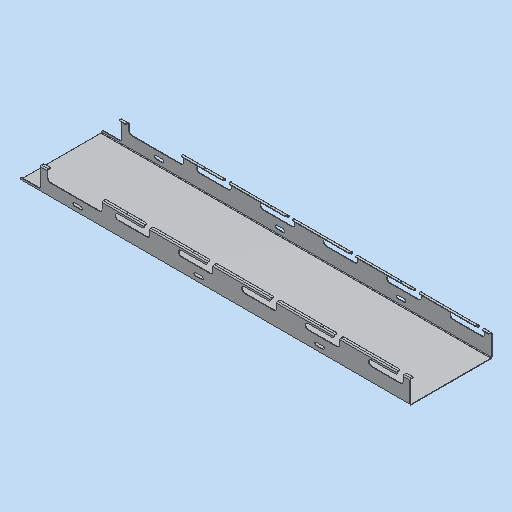
# Autodesk Inventor part: MM0948AN170_G01_103
Saved by Autodesk Inventor 2023.3 (Build 273359000, 359)
## iProperties
Part Number: MM0948AN170_G01_103
Material: 3.1645 AlCu4PbMgMn - AW 2007
Description: =<RBPARTNOTITLE2>
Document SubType Name: Blech
Designer: Benutzer
Mass: 3193.82 g
Surface Area: 11343.8 cm^2
Volume: 1120.64 cm^3
Density: 2.85 g/cm^3
Sheet Metal Rule: Standard_mm
Appearance: Aluminium AnP
Vendor: ASW
Flat Pattern Width: 135.4 cm
Flat Pattern Length: 45.5096 cm
Flat Pattern Area: 6161.99 cm^2
Sheet Metal Width: 1354,000 mm
Sheet Metal Length: 455,096 mm
Sheet Metal Area: 616199,407 mm^2
Created: 2023-03-23
RBCHANGEDESCRIPTION1: Erstfreigabe
RBCHANGENO1: 00
RBDOCUMENTTYPE: DRF
RBDOCUMENTVERSION: 00
RBDRAWINGMAINSCALE: 1:1
RBDRAWINGMISSINGSPEC: --
RBDRAWINGVOLUME: --
RBDSV1: 0850
RBGBDETAILS: 43274
RBGBEDGESIN1: +0,5
RBGBEDGESIN2: +0,2
RBGBEDGESOUT1: -0,3
RBGBEDGESOUT2: -0,1
RBMATERIAL: =<Material>
RBMATMEETS: --
RBMATNO: =<Part Number>
RBORGUNITRESPONSIBLE1: AnP/TEF1
RBPARTMADEOF: 2 x 1354 x 455,096 (FM)
RBPARTNO: SIEHE MNR
RBPARTNOTITLE1: manufactured part
RBPARTNOTITLE2: Anfertigungsteil
RBPARTSAFETYINDICATOR: --
RBSURFACE: --
RBSURFACE2: --
RBZEDGESNORM: ISO13715:2002-06
RBZGENDIMCLASS: m
RBZGENDIMNORM: ISO 2768-1:1989-11
RBZGENGEOCLASS: H
RBZGENGEONORM: ISO 2768-2:1989-11
RBZSURFACENORM: ISO13D2:2002-02
RBZTOLERANCENORM: ISO 14405-1:2010-12
AnP_Material: =<Material>
AnP_TemplVers: 20190222
AnP_Kategorie: 1
MaxAbmaße: 2 x 1354 x 455,096 (FM)
AnP_Kommentar_aktuell: =<Comments>
AnP_Material_aktuell: =<Material>
Author: FH/Wi
Keywords: =<RBPARTMADEOF>
Comments: =<RBSURFACE2>
Revision Number: 01
Autodesk Inventor part; units mm, degrees
ref_plane "YZ Plane" through (0, 0, 0) normal (1, 0, 0) x (0, 1, 0)
ref_plane "XZ Plane" through (0, 0, 0) normal (0, 1, 0) x (-1, 0, 0)
sketch "Skizze1" plane through (0, 0, 0) normal (0, 0, 1) x (1, 0, 0)
  line L0 (0, 0) -> (1654, 0)
  line L1 (1654, 0) -> (1654, 285)
  line L2 (1654, 285) -> (0, 285)
  line L3 (0, 285) -> (0, 0)
  dimension "d0" = 1654
  dimension "d1" = 285
  constraints: 8 end point, 2 parallel, 1 horizontal, 1 perpendicular
  measures "d0" distance of L2.end L1.end
  measures "d1" distance of L1.end L0.end
extrude "Extrusion1" add sketch "Skizze1" along normal blind 2
sketch "Skizze2" plane through (0, 283, 0) normal (0, 1, 0) x (-1, 0, 0)
  line L0 (-1654, 0) -> (0, 0)
  line L1 (0, 0) -> (0, 80)
  line L2 (0, 80) -> (-1654, 80)
  line L3 (-1654, 80) -> (-1654, 0)
  constraints: 4 end point, 4 other
edge flange "Lasche1" height 80 angle 90 thickness 2 bend radius 2 thickness toward (0, 1, 0) relief tear relief width 2 relief depth 1 edges at (827, 285, 2) wall of the first edge with corners at (1654, 283, 0) (0, 283, 0) (0, 283, 80) (1654, 283, 80)
bend "Biegung1"
corner "Ecke1"
sketch "Skizze3" plane through (0, 285, 78) normal (0, 0, 1) x (1, 0, 0)
  line L0 (1654, 0) -> (0, 0)
  line L1 (0, 0) -> (0, -12)
  line L2 (0, -12) -> (1654, -12)
  line L3 (1654, -12) -> (1654, 0)
  constraints: 4 end point, 4 other
edge flange "Lasche2" height 12 angle 90 thickness 2 bend radius 2 thickness toward (0, 0, 1) relief tear relief width 2 relief depth 1 edges at (827, 283, 80) wall of the first edge with corners at (1654, 285, 78) (0, 285, 78) (0, 273, 78) (1654, 273, 78)
bend "Biegung2"
corner "Ecke2"
sketch "Skizze4" plane through (1654, 2, 0) normal (0, -1, 0) x (1, 0, 0)
  line L0 (-1654, 0) -> (0, 0)
  line L1 (0, 0) -> (0, 40)
  line L2 (0, 40) -> (-1654, 40)
  line L3 (-1654, 40) -> (-1654, 0)
  constraints: 4 end point, 4 other
edge flange "Lasche3" height 40 angle 90 thickness 2 bend radius 2 thickness toward (0, -1, 0) relief tear relief width 2 relief depth 1 edges at (827, 0, 2) wall of the first edge with corners at (0, 2, 0) (1654, 2, 0) (1654, 2, 40) (0, 2, 40)
bend "Biegung3"
corner "Ecke3"
sketch "Skizze6" plane through (0, 0, 40) normal (0, -1, 0) x (1, 0, 0)
  line L0 (0, -36) -> (1654, -36) projected
  line L1 (1654, 0) -> (1654, -36) projected
  line L2 (0, 0) -> (1654, 0) projected
  line L3 (0, -36) -> (0, 0) projected
  line L4 (140, 0) -> (140, -32)
  line L5 (140, -32) -> (1514, -32)
  line L6 (1514, -32) -> (1514, 0)
  point P0 (0, -40)
  dimension "d43" = 140
  dimension "d44" = 140
  dimension "d45" = 32
  constraints: 6 end point, 2 perpendicular, 2 point on line, 1 vertical
  measures "d43" distance between parallel lines of L3 L4
  measures "d44" distance between parallel lines of L1 L6
  measures "d45" distance between parallel lines of L5 L2
extrude "Extrusion3" cut sketch "Skizze6" against normal blind 2 contours L2 L6 L5 L4
sketch "Skizze10" plane through (140, 0, 8) normal (0, 0, 1) x (1, 0, 0)
  line L0 (1374, 0) -> (0, 0) projected
  line L1 (1374, 0) -> (1374, 2) projected
  line L2 (0, 2) -> (1374, 2) projected
  line L3 (0, 0) -> (0, 2) projected
  point P0 (-140, 0)
extrude "Extrusion5" add sketch "Skizze10" along normal up to surface (32 mm away)
sketch "Skizze11" plane through (0, 0, 40) normal (0, 0, 1) x (1, 0, 0)
  line L0 (0, 0) -> (1654, 0) projected
  line L1 (1654, 2) -> (1654, 0) projected
  line L2 (0, 2) -> (1654, 2) projected
  line L3 (0, 2) -> (0, 0) projected
  point P0 (0, 0)
extrude "Extrusion6" add sketch "Skizze11" along normal up to surface (36 mm away)
sketch "Skizze12" plane through (1654, 4, 78) normal (0, 0, 1) x (1, 0, 0)
  line L0 (-1654, 0) -> (0, 0)
  line L1 (0, 0) -> (0, 8)
  line L2 (0, 8) -> (-1654, 8)
  line L3 (-1654, 8) -> (-1654, 0)
  constraints: 4 end point, 4 other
edge flange "Lasche4" height 12 angle 90 thickness 2 bend radius 2 thickness toward (0, 0, 1) relief tear relief width 2 relief depth 1 edges at (827, 2, 76) wall of the first edge with corners at (0, 4, 78) (1654, 4, 78) (1654, 12, 78) (0, 12, 78)
bend "Biegung4"
corner "Ecke4"
sketch "Skizze18" plane through (0, 0, 4) normal (0, -1, 0) x (1, 0, 0)
  line L0 (120, 56) -> (220, 56) construction
  line L1 (120, 46) -> (220, 46)
  line L2 (220, 66) -> (120, 66)
  arc A0 (120, 66) -> (120, 46) centre (120, 56) ccw
  arc A1 (220, 46) -> (220, 66) centre (220, 56) ccw
  line L3 (0, 76) -> (1654, 76) projected
  line L4 (1654, 72) -> (0, 72) projected
  line L5 (0, 0) -> (0, 72) projected
  line L6 (0, 0) -> (1654, 0) projected
  line L7 (1654, 72) -> (1654, 0) projected
  line L8 (1654, 72) -> (0, 72) projected
  line L9 (230, 56) -> (230, 76)
  line L10 (210, 66) -> (210, 76)
  point P0 (0, -4)
  point P1 (170, 56)
  dimension "d126" = 100
  dimension "d127" = 20
  dimension "d128" = 20
  dimension "d129" = 20
  dimension "d136" = 120
  constraints: 12 end point, 5 point on circle, 4 tangent, 3 point on line, 2 centre point, 2 perpendicular, 1 horizontal, 1 midpoint, 1 parallel
  measures "d126" distance of L0.start L0.end
  measures "d127" diameter of A1
  measures "d128" distance from line of point (170, 56) L3
  measures "d129" distance between parallel lines of L9 L10
  measures "d136" distance from line of L0.start L5
extrude "Extrusion9" cut sketch "Skizze18" against normal blind 1209 contours A0 L2 A1 L1 | A1 L2 L10 L4 L9 | L4 L10 L3 L9
fillet "Rundung1" radius 5 1 edges at (210, 1, 70)
fillet "Rundung2" radius 5 5 edges at (230, 273, 79) (210, 273, 79) (210, 284, 70) (210, 12, 79) (230, 12, 79)
pattern_linear "Rechteckige Anordnung2" count 7 spacing 220 along (1, 0, 0) of "Extrusion9"
fillet "Rundung3" radius 5 21 edges at (430, 1, 70) (430, 12, 79) (450, 12, 79) (430, 273, 79) (430, 284, 70) (450, 273, 79) (650, 273, 79) (650, 284, 70) (670, 273, 79) (650, 1, 70) (650, 12, 79) (670, 12, 79) (870, 1, 70) (870, 12, 79) (890, 12, 79) (1090, 1, 70) (1090, 12, 79) (1110, 12, 79) (1310, 1, 70) (1310, 12, 79) (1330, 12, 79)
fillet "Rundung4" radius 5 17 edges at (1530, 1, 70) (1530, 12, 79) (1550, 12, 79) (1654, 12, 79) (1654, 273, 79) (1550, 273, 79) (1530, 273, 79) (1530, 284, 70) (1310, 273, 79) (1310, 284, 70) (1330, 273, 79) (1090, 273, 79) (1090, 284, 70) (1110, 273, 79) (870, 273, 79) (870, 284, 70) (890, 273, 79)
sketch "Skizze19" plane through (0, 285, 4) normal (0, 1, 0) x (1, 0, 0)
  line L0 (189, -18.5) -> (211, -18.5) construction
  line L1 (189, -24) -> (211, -24)
  line L2 (211, -13) -> (189, -13)
  arc A0 (189, -13) -> (189, -24) centre (189, -18.5) ccw
  arc A1 (211, -24) -> (211, -13) centre (211, -18.5) ccw
  line L3 (1984.8, 4) -> (-330.8, 4) projected
  line L4 (0, -72) -> (0, 0) projected
  point P0 (0, 4)
  point P1 (200, -18.5)
  dimension "d144" = 22
  dimension "d145" = 11
  dimension "d146" = 22.5
  dimension "d147" = 200
  constraints: 8 end point, 4 point on circle, 4 tangent, 2 centre point, 1 horizontal, 1 midpoint, 1 parallel
  measures "d144" distance of L0.start L0.end
  measures "d145" diameter of A1
  measures "d146" distance from line of L3 point (200, -18.5)
  measures "d147" distance from line of point (200, -18.5) L4
extrude "Extrusion10" cut sketch "Skizze19" against normal through all
pattern_linear "Rechteckige Anordnung3" count 4 spacing 420 along (1, 0, 0) of "Extrusion10"
sketch "Skizze21" plane through (0, 0, 0) normal (0, 1, 0) x (-1, 0, 0)
  line L0 (-210, 80) -> (0, 80) projected
  line L1 (0, 76) -> (0, 4) projected
  line L2 (0, 76) -> (-210, 76) projected
  line L3 (-1984.8, 0) -> (330.8, 0) projected
  line L4 (-1654, 4) -> (0, 4) projected
  line L5 (-1449, 17) -> (-1471, 17) projected
  arc A0 (-1471, 28) -> (-1471, 17) centre (-1471, 22.5) ccw projected
  line L6 (-1471, 28) -> (-1449, 28) projected
  arc A1 (-1449, 17) -> (-1449, 28) centre (-1449, 22.5) ccw projected
  line L7 (-1029, 17) -> (-1051, 17) projected
  arc A2 (-1051, 28) -> (-1051, 17) centre (-1051, 22.5) ccw projected
  line L8 (-1051, 28) -> (-1029, 28) projected
  arc A3 (-1029, 17) -> (-1029, 28) centre (-1029, 22.5) ccw projected
  line L9 (-609, 17) -> (-631, 17) projected
  arc A4 (-631, 28) -> (-631, 17) centre (-631, 22.5) ccw projected
  line L10 (-631, 28) -> (-609, 28) projected
  arc A5 (-609, 17) -> (-609, 28) centre (-609, 22.5) ccw projected
  arc A6 (-211, 28) -> (-211, 17) centre (-211, 22.5) ccw projected
  line L11 (-211, 28) -> (-189, 28) projected
  arc A7 (-189, 17) -> (-189, 28) centre (-189, 22.5) ccw projected
  line L12 (-189, 17) -> (-211, 17) projected
  arc A8 (-870, 75) -> (-865, 70) centre (-865, 75) ccw projected
  line L13 (-865, 70) -> (-780, 70) projected
  arc A9 (-780, 50) -> (-780, 70) centre (-780, 60) ccw projected
  line L14 (-780, 50) -> (-880, 50) projected
  arc A10 (-890, 60) -> (-880, 50) centre (-880, 60) ccw projected
  line L15 (-890, 60) -> (-890, 76) projected
  line L16 (-890, 76) -> (-1090, 76) projected
  line L17 (-1090, 76) -> (-1090, 75) projected
  arc A11 (-1090, 75) -> (-1085, 70) centre (-1085, 75) ccw projected
  line L18 (-1085, 70) -> (-1000, 70) projected
  arc A12 (-1000, 50) -> (-1000, 70) centre (-1000, 60) ccw projected
  line L19 (-1000, 50) -> (-1100, 50) projected
  arc A13 (-1110, 60) -> (-1100, 50) centre (-1100, 60) ccw projected
  line L20 (-1110, 60) -> (-1110, 76) projected
  line L21 (-1110, 76) -> (-1310, 76) projected
  line L22 (-1310, 76) -> (-1310, 75) projected
  arc A14 (-1310, 75) -> (-1305, 70) centre (-1305, 75) ccw projected
  line L23 (-1305, 70) -> (-1220, 70) projected
  arc A15 (-1220, 50) -> (-1220, 70) centre (-1220, 60) ccw projected
  line L24 (-1220, 50) -> (-1320, 50) projected
  arc A16 (-1330, 60) -> (-1320, 50) centre (-1320, 60) ccw projected
  line L25 (-1330, 60) -> (-1330, 76) projected
  line L26 (-1330, 76) -> (-1530, 76) projected
  line L27 (-1530, 76) -> (-1530, 75) projected
  arc A17 (-1530, 75) -> (-1525, 70) centre (-1525, 75) ccw projected
  line L28 (-1525, 70) -> (-1440, 70) projected
  arc A18 (-1440, 50) -> (-1440, 70) centre (-1440, 60) ccw projected
  line L29 (-1440, 50) -> (-1540, 50) projected
  arc A19 (-1550, 60) -> (-1540, 50) centre (-1540, 60) ccw projected
  line L30 (-1550, 60) -> (-1550, 76) projected
  line L31 (-1550, 76) -> (-1654, 76) projected
  line L32 (-1654, 4) -> (-1654, 76) projected
  line L33 (-1654, 4) -> (0, 4) projected
  line L34 (0, 76) -> (0, 4) projected
  line L35 (0, 76) -> (-210, 76) projected
  line L36 (-210, 76) -> (-210, 75) projected
  arc A20 (-210, 75) -> (-205, 70) centre (-205, 75) ccw projected
  line L37 (-205, 70) -> (-120, 70) projected
  arc A21 (-120, 50) -> (-120, 70) centre (-120, 60) ccw projected
  line L38 (-120, 50) -> (-220, 50) projected
  arc A22 (-230, 60) -> (-220, 50) centre (-220, 60) ccw projected
  line L39 (-230, 60) -> (-230, 76) projected
  line L40 (-230, 76) -> (-430, 76) projected
  line L41 (-430, 76) -> (-430, 75) projected
  arc A23 (-430, 75) -> (-425, 70) centre (-425, 75) ccw projected
  line L42 (-425, 70) -> (-340, 70) projected
  arc A24 (-340, 50) -> (-340, 70) centre (-340, 60) ccw projected
  line L43 (-340, 50) -> (-440, 50) projected
  arc A25 (-450, 60) -> (-440, 50) centre (-440, 60) ccw projected
  line L44 (-450, 60) -> (-450, 76) projected
  line L45 (-450, 76) -> (-650, 76) projected
  line L46 (-650, 76) -> (-650, 75) projected
  arc A26 (-650, 75) -> (-645, 70) centre (-645, 75) ccw projected
  line L47 (-645, 70) -> (-560, 70) projected
  arc A27 (-560, 50) -> (-560, 70) centre (-560, 60) ccw projected
  line L48 (-560, 50) -> (-660, 50) projected
  arc A28 (-670, 60) -> (-660, 50) centre (-660, 60) ccw projected
  line L49 (-670, 60) -> (-670, 76) projected
  line L50 (-670, 76) -> (-870, 76) projected
  line L51 (-870, 76) -> (-870, 75) projected
  line L52 (-70, 80) -> (-70, 10)
  line L53 (-70, 10) -> (0, 10)
  line L54 (0, 80) -> (-70, 80)
  line L55 (0, 10) -> (0, 80)
  point P0 (0, 0)
  dimension "d155" = 70
  dimension "d156" = 10
  constraints: 8 end point, 2 collinear, 2 perpendicular, 2 point on line
  measures "d155" distance between parallel lines of L1 L52
  measures "d156" distance between parallel lines of L3 L53
extrude "Extrusion11" cut sketch "Skizze21" along normal through all contours L0 L55 L2 L52 | L2 L1 L53 L52
fillet "Rundung5" radius 5 6 edges at (70, 1, 10) (0, 1, 10) (70, 12, 79) (70, 273, 79) (70, 284, 10) (0, 284, 10)
ref_plane "Arbeitsebene2" through (0, 0, 80) normal (0, 0, 1) x (1, 0, 0)
sketch "Skizze22" plane through (0, 0, 80) normal (0, 0, 1) x (1, 0, 0)
  line L0 (205, 273) -> (75, 273) projected
  line L1 (210, 281) -> (70, 281) projected
  line L2 (70, 4) -> (210, 4) projected
  line L3 (75, 12) -> (205, 12) projected
  line L4 (0, 342) -> (0, -57) projected
  line L5 (-42, 0) -> (252, 0) projected
  line L6 (5, 285) -> (65, 285) projected
  line L7 (70, 285) -> (210, 285) projected
  line L8 (210, 278) -> (210, 281) projected
  line L9 (70, 281) -> (70, 278) projected
  point P0 (0, 0)
  point P1 (1495, 277)
  point P2 (1495, 8)
  dimension "d161" = 269
  dimension "d162" = 285
  dimension "d163" = 8
  dimension "d164" = 1495
  dimension "d165" = 140
  dimension "d166" = 70
  constraints: 1 vertical alignment
  measures "d161" distance of point (1495, 8) point (1495, 277)
  measures "d162" distance between parallel lines of L5 L6
  measures "d163" distance from line of point (1495, 277) L7
  measures "d164" distance from line of L4 point (1495, 277)
  measures "d165" distance between parallel lines of L8 L9
  measures "d166" distance from line of L9.end L4
hole "Bohrung4" at (1495, 277, 80) at (1495, 8, 80) direction (0, 0, -1) diameter 3.242 depth 11.8 tip angle 118 thread size "M4x0.7" designation "M4" class "6H" standard "ISO Metric profile"
pattern_linear "Rechteckige Anordnung4" count 3 spacing 450 along (-1, 0, 0) of "Bohrung4"
pattern_linear "Rechteckige Anordnung5" count 2 spacing 1130 along (-1, 0, 0) of "Bohrung4"
sketch "Skizze28" plane through (0, 0, 0) normal (0, 0, -1) x (-1, 0, 0)
  line L0 (-1654, 4) -> (-1654, 281) projected
  line L1 (-1654, 4) -> (0, 4) projected
  line L2 (0, 281) -> (0, 4) projected
  line L3 (0, 281) -> (-1654, 281) projected
  line L4 (-1654, 4) -> (-1654, 281) projected
  line L5 (-1654, -17.1903) -> (-1354, -17.1903)
  line L6 (-1354, -17.1903) -> (-1354, 304.3639)
  line L7 (-1354, 304.3639) -> (-1654, 304.3639)
  line L8 (-1654, 304.3639) -> (-1654, -17.1903)
  point P0 (0, 0)
  dimension "d193" = 300
  dimension "d194" = 300
  constraints: 8 end point, 2 parallel, 1 horizontal, 1 perpendicular
  measures "d193" distance of L7.end L6.end
  measures "d194" distance between parallel lines of L6 L0
extrude "Extrusion17" cut sketch "Skizze28" against normal through all contours L0 L3 L6 L1 | L1 L6 L5 L8 | L8 L7 L6 L3
sketch "Skizze29" plane through (120, 0, 50) normal (0, -1, 0) x (1, 0, 0)
  line L0 (-25, -5) -> (165, -5)
  line L1 (165, -5) -> (165, 30)
  line L2 (165, 30) -> (-25, 30)
  line L3 (-25, 30) -> (-25, -5)
  arc A0 (0, 20) -> (0, 0) centre (0, 10) ccw projected
  line L4 (100, 0) -> (0, 0) projected
  line L5 (-50, 30) -> (90, 30) projected
  line L6 (-120, -46) -> (-120, -50) projected
  dimension "d202" = 25
  dimension "d204" = 5
  dimension "d206" = 285
  constraints: 8 end point, 2 parallel, 1 horizontal, 1 perpendicular, 1 point on line
  measures "d202" distance from line of L3 A0.centre
  measures "d204" distance between parallel lines of L0 L4
  measures "d206" distance between parallel lines of L6 L1
extrude "Extrusion18" cut sketch "Skizze29" against normal through all
fillet "Rundung7" radius 4 4 edges at (95, 12, 79) (95, 273, 79) (285, 12, 79) (285, 273, 79)
fillet "Eckenrundung1" radius 10 4 edges at (95, 284, 45) (95, 1, 45) (285, 284, 45) (285, 1, 45)
equation "\"d4\" = BreiteBiegungsfreistellung"
equation "\"d5\" = TiefeBiegungsfreistellung"
equation "\"d6\" = MinimalRest"
equation "\"d7\" = Biegeradius"
equation "\"d10\" = Biegeradius"
equation "\"d11\" = GrößeEckenfreistellung"
equation "\"d12\" = Abstandsgröße"
equation "\"d13\" = JacobiRadiusGröße"
equation "\"d14\" = BreiteBiegungsfreistellung"
equation "\"d15\" = TiefeBiegungsfreistellung"
equation "\"d16\" = MinimalRest"
equation "\"d17\" = Biegeradius"
equation "\"d20\" = Biegeradius"
equation "\"d21\" = GrößeEckenfreistellung"
equation "\"d22\" = Abstandsgröße"
equation "\"d23\" = JacobiRadiusGröße"
equation "\"d24\" = BreiteBiegungsfreistellung"
equation "\"d25\" = TiefeBiegungsfreistellung"
equation "\"d26\" = MinimalRest"
equation "\"d27\" = Biegeradius"
equation "\"d30\" = Biegeradius"
equation "\"d31\" = GrößeEckenfreistellung"
equation "\"d32\" = Abstandsgröße"
equation "\"d33\" = JacobiRadiusGröße"
equation "\"d100\" = BreiteBiegungsfreistellung"
equation "\"d101\" = TiefeBiegungsfreistellung"
equation "\"d102\" = MinimalRest"
equation "\"d103\" = Biegeradius"
equation "\"d106\" = Biegeradius"
equation "\"d107\" = GrößeEckenfreistellung"
equation "\"d108\" = Abstandsgröße"
equation "\"d109\" = JacobiRadiusGröße"
equation "\"Biegeradius\" = Stärke"
equation "\"BreiteBiegungsfreistellung\" = Stärke"
equation "\"TiefeBiegungsfreistellung\" = 0.5 * Stärke"
equation "\"GrößeEckenfreistellung\" = 4 * Stärke"
equation "\"MinimalRest\" = 2 * Stärke"
equation "\"Übergangsradius\" = Biegeradius"
equation "\"JacobiRadiusGröße\" = Biegeradius"
equation "\"Abstandsgröße\" = Stärke"
equation "\"Stärke\" = 2"
